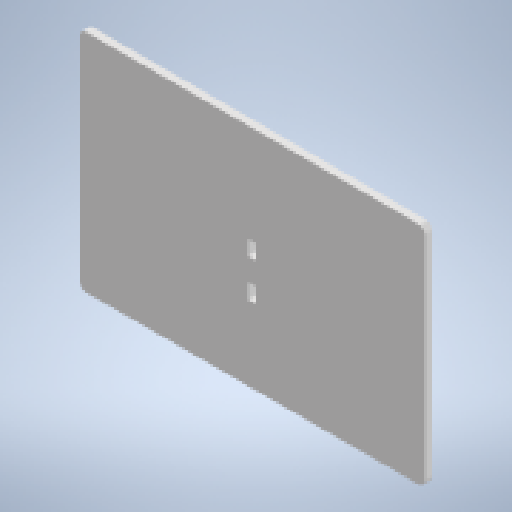
# Autodesk Inventor part: StandBottom
Saved by Autodesk Inventor 2025.2 (Build 292293000, 293)
## iProperties
Created: 2025-07-03
Part Number: StandBottom
Material: Generic
Document SubType Name: Modeling
Designer: ricoa
Density: 1 g/cm^3
Appearance: Default
Author: ricoa
Autodesk Inventor part; units mm, degrees
ref_plane "YZ Plane" through (0, 0, 0) normal (1, 0, 0) x (0, 1, 0)
ref_plane "XZ Plane" through (0, 0, 0) normal (0, 1, 0) x (-1, 0, 0)
ref_plane "XY Plane" through (0, 0, 0) normal (0, 0, 1) x (1, 0, 0)
sketch "Sketch1" plane through (0, 0, 0) normal (0, 0, 1) x (1, 0, 0)
  line L0 (157.9755, -112.7043) -> (97.9755, -112.7043) projected
  line L1 (162.9755, -247.7043) -> (162.9755, -117.7043) projected
  line L2 (7.9755, -247.7043) -> (7.9755, -117.7043) projected
  line L3 (97.9755, -252.7043) -> (157.9755, -252.7043) projected
  line L4 (0, 10) -> (-5, 10) projected
  line L5 (-5, 10) -> (-5, 0) projected
  line L6 (-5, 0) -> (0, 0) projected
  line L7 (0, 0) -> (0, 10) projected
  line L8 (-5, -25) -> (0, -25) projected
  line L9 (0, -25) -> (0, -15) projected
  line L10 (0, -15) -> (-5, -15) projected
  line L11 (-5, -15) -> (-5, -25) projected
  line L12 (-5, 20) -> (0, 20) projected
  line L13 (0, -35) -> (-5, -35) projected
  line L14 (-2.5, 20) -> (-2.5, -35) construction
  line L15 (-2.5, -7.5) -> (112.5, -7.5)
  line L16 (-2.5, 0) -> (-2.5, -75) construction
  line L17 (-117.5, 75) -> (112.5, 75)
  line L18 (112.5, 75) -> (112.5, -75)
  line L19 (112.5, -75) -> (-117.5, -75)
  line L20 (-117.5, -75) -> (-117.5, 75)
  line L21 (-117.5, 75) -> (112.5, -75) construction
  line L22 (112.5, 75) -> (-117.5, -75) construction
  dimension "d0" = 115
  dimension "d1" = 75
  constraints: 18 end point, 6 midpoint, 2 horizontal, 2 parallel, 2 point on line, 1 perpendicular
  measures "d0" distance of L15.start L15.end
  measures "d1" distance of L16.start L16.end
extrude "Extrusion1" add sketch "Sketch1" along normal blind 5
fillet "Fillet1" radius 5 4 edges at (112.5, 75, 2.5) (-117.5, 75, 2.5) (112.5, -75, 2.5) (-117.5, -75, 2.5)
body "Solid1"
